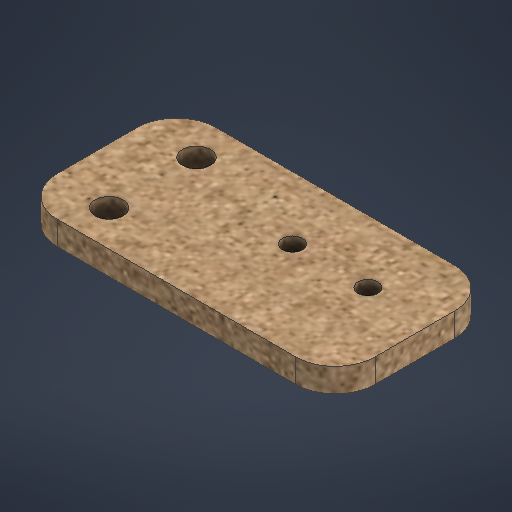
# Autodesk Inventor part: LimitSwitchMountPlate
Saved by Autodesk Inventor 2027.1 (Build 311270010, 270A)
## iProperties
Created: 2026-10-16
Part Number: LimitSwitchMountPlate
Material: MDF Medium Density Fiberboard
Document SubType Name: Modeling
Designer: SDS Scholar
Density: 0.8 g/cm^3
Appearance: Cardboard - Corrugated
Author: SDS Scholar
Autodesk Inventor part; units mm, degrees
ref_plane "YZ Plane" through (0, 0, 0) normal (1, 0, 0) x (0, 1, 0)
ref_plane "XZ Plane" through (0, 0, 0) normal (0, 1, 0) x (-1, 0, 0)
ref_plane "XY Plane" through (0, 0, 0) normal (0, 0, 1) x (1, 0, 0)
sketch "Sketch1" plane through (0, 0, 0) normal (0, 1, 0) x (-1, 0, 0)
  line L0 (15, 10) -> (-15, 10)
  line L1 (-20, 5) -> (-20, -5)
  line L2 (-15, -10) -> (15, -10)
  line L3 (20, -5) -> (20, 5)
  circle A0 centre (-2.5, -2.1) radius 1.25
  circle A1 centre (-12, -2.1) radius 1.25
  arc A2 (-15, 10) -> (-20, 5) centre (-15, 5) ccw
  arc A3 (-20, -5) -> (-15, -10) centre (-15, -5) ccw
  arc A4 (20, 5) -> (15, 10) centre (15, 5) ccw
  arc A5 (15, -10) -> (20, -5) centre (15, -5) ccw
  circle A6 centre (13, -5.5) radius 1.75
  circle A7 centre (13, 5.5) radius 1.75
  line L4 (20, 0) -> (-20, 0) construction
  point P0 (0, 0)
  point P1 (-20, -10)
  point P2 (-20, 10)
  point P3 (20, -10)
  point P4 (0, -10)
  dimension "d0" = 40
  dimension "d1" = 20
  dimension "d2" = 2.5
  dimension "d3" = 2.5
  dimension "d4" = 9.5
  dimension "d5" = 7.9
  dimension "d6" = 8
  dimension "d7" = 5
  dimension "d10" = 3.5
  dimension "d11" = 3.5
  dimension "d12" = 7
  dimension "d13" = 4.5
  constraints: 10 end point, 8 centre point, 8 point on circle, 8 tangent, 6 point on line, 3 equal radius, 3 midpoint, 2 horizontal alignment, 2 parallel, 2 vertical alignment, 1 horizontal, 1 perpendicular, 1 symmetric about line
  measures "d0" distance of point (20, -10) point (-20, -10)
  measures "d1" distance of point (-20, 10) point (-20, -10)
  measures "d2" diameter of A0
  measures "d3" diameter of A1
  measures "d4" distance of A1.centre A0.centre
  measures "d5" distance from line of L2 A0.centre
  measures "d6" distance from line of L1 A1.centre
  measures "d7" radius of A2
  measures "d10" diameter of A6
  measures "d11" diameter of A7
  measures "d12" distance from line of L3 A6.centre
  measures "d13" distance from line of L2 A6.centre
extrude "Extrusion1" add sketch "Sketch1" along normal blind 3
body "Solid1"
